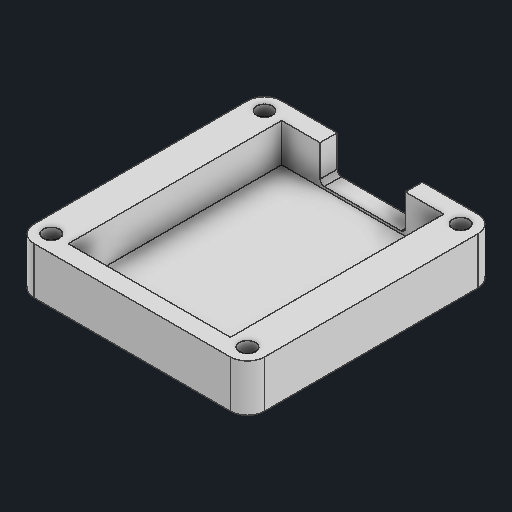
# Autodesk Inventor part: c3 case
Saved by Autodesk Inventor 2027 (Build 310192000, 192)
## iProperties
Created: 2026-09-27
Part Number: c3 case
Material: 일반
Document SubType Name: Modeling
Designer: work
Density: 1 g/cm^3
Appearance: 기본값
Author: work
Autodesk Inventor part; units mm, degrees
ref_plane "YZ Plane" through (0, 0, 0) normal (1, 0, 0) x (0, 1, 0)
ref_plane "XZ Plane" through (0, 0, 0) normal (0, 1, 0) x (-1, 0, 0)
ref_plane "XY Plane" through (0, 0, 0) normal (0, 0, 1) x (1, 0, 0)
sketch "스케치1" plane through (0, 0, 0) normal (0, 1, 0) x (-1, 0, 0)
  line L0 (0, 0) -> (19, 0)
  line L1 (19, 0) -> (19, -25)
  line L2 (19, -25) -> (0, -25)
  line L3 (0, -25) -> (0, 0)
  line L4 (14.5, -25) -> (4.5, -25)
  line L5 (4.5, -25) -> (4.5, -27)
  line L6 (4.5, -27) -> (14.5, -27)
  line L7 (14.5, -27) -> (14.5, -25)
  line L8 (21, -27) -> (21, 2)
  line L9 (21, 2) -> (-2, 2)
  line L10 (-2, 2) -> (-2, -27)
  line L11 (-2, -27) -> (21, -27)
  point P0 (19, -12.5)
  point P1 (14.5, -26)
  point P2 (9.5, -27)
  point P3 (4.5, -25)
  dimension "d0" = 19
  dimension "d1" = 25
  dimension "d2" = 2
  dimension "d3" = 10
  constraints: 24 end point, 6 parallel, 4 midpoint, 3 perpendicular, 2 horizontal, 1 point on line, 3 other
  measures "d0" distance of L1.end L2.end
  measures "d1" distance of L0.end L1.end
  measures "d2" distance from line of point (19, -12.5) L8
  measures "d3" distance from line of L5 point (14.5, -26)
extrude "돌출1" add sketch "스케치1" along normal blind 1.3 contours L2 L7 L6 L5
extrude "돌출2" add sketch "스케치1" along normal blind 1 contours L0 L1 L2 L3
extrude "돌출3" add sketch "스케치1" along normal blind 5.5 contours L3 L2 L5 L11 L10 L9 L8 L7 L1 L0
sketch "스케치2" plane through (0, 5.5, 0) normal (0, 1, 0) x (1, 0, 0)
  line L0 (-21, 27) -> (-21, -2) projected
  circle A0 centre (-21, 0) radius 0.95
  line L1 (-4.5, 27) -> (-14.5, 27) projected
  line L2 (-9.5, 27) -> (-9.5, -2) construction
  line L3 (-21, -2) -> (2, -2) projected
  circle A1 centre (-21, 25) radius 0.95
  line L4 (-21, 0) -> (-21, 25) construction
  line L5 (-19, 0) -> (-19, 25)
  line L6 (-23, 25) -> (-23, 0)
  arc A2 (-23, 0) -> (-19, 0) centre (-21, 0) ccw
  arc A3 (-19, 25) -> (-23, 25) centre (-21, 25) ccw
  line L7 (2, 27) -> (2, -2)
  circle A4 centre (2, 0) radius 0.95
  line L8 (-14.5, 27) -> (-4.5, 27)
  line L9 (2, -2) -> (-21, -2)
  circle A5 centre (2, 25) radius 0.95
  line L10 (2, 0) -> (2, 25) construction
  line L11 (0, 0) -> (0, 25)
  line L12 (4, 25) -> (4, 0)
  arc A6 (0, 0) -> (4, 0) centre (2, 0) ccw
  arc A7 (4, 25) -> (0, 25) centre (2, 25) ccw
  point P0 (0, 0)
  point P1 (-21, 12.5)
  point P2 (2, 12.5)
  point P3 (-21, -0.95)
  point P4 (-21, 0.95)
  point P5 (-21, 24.05)
  point P6 (-21, 25.95)
  point P7 (2, 25.95)
  point P8 (2, 24.05)
  point P9 (2, 0.95)
  point P10 (2, -0.95)
  point P11 (2, -2)
  dimension "d10" = 1.9
  dimension "d11" = 2
  dimension "d12" = 1.9
  dimension "d13" = 2
  constraints: 24 end point, 12 symmetric about line, 9 point on circle, 8 centre point, 4 point on line, 4 tangent, 3 midpoint, 1 parallel, 4 other
  measures "d10" diameter of A0
  measures "d11" distance of L0.end L4.start
  measures "d12" diameter of A1
  measures "d13" distance of L0.start L4.end
extrude "돌출4" add sketch "스케치2" against normal up to surface (5.5 mm away) contours L7 A4 A5 A7 L12 A6 | L0 A1 A0 A2 L6 A3
extrude "돌출5" cut sketch "스케치2" against normal blind 10 contours A1 L0 | A0 L0 | A4 L7 | A5 L7 picked at (-20.7524, 25.1974) picked at (-20.7147, 0.1374) picked at (1.9242, -0.3075) picked at (1.7771, 25.2896)
sketch "스케치3" plane through (0, 0, 0) normal (0, -1, 0) x (1, 0, 0)
  circle A0 centre (2, -25) radius 0.95 projected
  circle A1 centre (2, 0) radius 0.95 projected
  circle A2 centre (-21, 0) radius 0.95 projected
  circle A3 centre (-21, -25) radius 0.95 projected
  arc A4 (-21, 2) -> (-23, 0) centre (-21, 0) ccw projected
  line L0 (-23, 0) -> (-23, -25) projected
  arc A5 (-23, -25) -> (-21, -27) centre (-21, -25) ccw projected
  line L1 (2, -27) -> (-21, -27) projected
  arc A6 (2, -27) -> (4, -25) centre (2, -25) ccw projected
  line L2 (4, -25) -> (4, 0) projected
  arc A7 (4, 0) -> (2, 2) centre (2, 0) ccw projected
  line L3 (-21, 2) -> (2, 2) projected
  point P0 (0, 0)
extrude "돌출6" add sketch "스케치3" against normal blind 3 contours A0 | A1 | A2 | A3
fillet "모깎기1" radius 0.5 2 edges at (-4.5, 1.3, -26) (-14.5, 1.3, -26)
